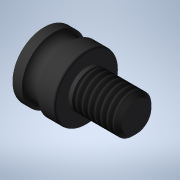
# Autodesk Inventor part: 101013DH-16-B1_ir
Saved by Autodesk Inventor 2021 (Build 250183000, 183)
## iProperties
Created: 2025-04-11
Part Number: 101013DH-16-B1_ir
Material: Generic
Catalog Web Link: www.cadenas.de
Description: DH-A,B,H ir-D-Series bearings
Vendor: TOKBEARING
Document SubType Name: Modeling
Designer: psAdmin
Manufacturer: TOKBEARING
Mass: 11800 g
Surface Area: 6.00448 cm^2
Volume: 0.745153 cm^3
Density: 1 g/cm^3
Appearance: PSOLRGB-175-175-175
Category: PARTsolutions
Company: TOKBEARING
Title: 101013DH-16-B1_ir
Author: Cadenas PARTsolutions
Comments: D-Series bearings
PSOL_IDENT_0: {$CADENAS_DATA/23d-libs/tok_bearing/d_series_bearings/dh_abh/dh_abh_ir.prj},181 {VTYP=3D},{NB=101013
PSOL_IDENT_1: DH-16-B1_ir},{LINA=101013DH-16-B1_ir},{NN=DH-A,B,H ir},{DATE=24.03.2025 06:05:05},{GEOMDATE=18.12.20
PSOL_IDENT_2: 12 09:46:00},{VERSION=},{LINEID=2630},{WBVAR=},{WBNUMERIC=}  {NB=101013DH-16-B1_ir},{LINA=101013DH-1
PSOL_IDENT_3: 6-B1_ir},{KT=DUMMY},{IDNR=},{CODE=101013},{PN=DH-16-B1},{D=19},{D1=16.0},{SD=-},{SDX=0.000},{SD1=-},
PSOL_IDENT_4: {SD1X=0.000},{W=6},{C=1},{CX=1.000},{L=8},{LX=8.000},{D2XT=-},{D2=0.000},{T=0.000},{G=2.1},{TYPE=2},
PSOL_IDENT_5: {QTY=2.000},{GW=11.8},{NDM=6.000},{BD=3},{OP=39.878},{N=6},{R=6.35},{GP=2.82}
NB: 101013DH-16-B1_ir
NN: DH-A,B,H ir
NT: D-Series bearings
NBSYN: $CODE.$PN._ir
LINA: 101013DH-16-B1_ir
CATALOG: TOK, Inc
CODE: 101013
PN: DH-16-B1
D: 19
D1: 16
SD: -
SD1: -
W: 6
C: 1
L: 8
D2XT: -
G: 2.1
TYPE: 2
QTY: 2.000
GW: 11.8
SUPPLIER: TOKBEARING
ARTICLENO: 101013DH-16-B1_ir
BOMINFO: 101013DH-16-B1_ir
CREATOR: CADENAS GmbH
Autodesk Inventor part; units mm, degrees
sketch "Sketch_2" plane through (0, 0, 0) normal (0, 0, 1) x (1, 0, 0)
  line L0 (15, 0) -> (0, 0)
  line L1 (0, 0) -> (0, 4.88)
  arc A0 (0.3, 5.18) -> (0, 4.88) centre (0.3, 4.88) ccw
  line L2 (0.3, 5.18) -> (1.701, 5.18)
  arc A1 (1.701, 5.18) -> (4.299, 5.18) centre (3, 5.93) ccw
  line L3 (4.299, 5.18) -> (6.7, 5.18)
  arc A2 (7, 4.88) -> (6.7, 5.18) centre (6.7, 4.88) ccw
  line L4 (7, 4.88) -> (7, 3)
  line L5 (7, 3) -> (14.3865, 3)
  line L6 (14.3865, 3) -> (15, 2.3865)
  line L7 (15, 2.3865) -> (15, 0)
  line L8 (15, 0) -> (0, 0)
  constraints: 18 end point, 6 point on circle, 3 centre point
revolve "Revolution1" add sketch "Sketch_2" angle 360 about axis through (15, 0, 0) along (1, 0, 0)
thread "Thread1" size "M6x1" class "6g" standard "ISO Metric profile" length 6.7865
sketch "Sketch_3" plane through (0, 0, 0) normal (0, 0, 1) x (1, 0, 0)
  line L0 (0, -3.5) -> (1.8209, -2.9084)
  line L1 (1.8209, -2.9084) -> (3.3, -0.3464)
  line L2 (3.3, -0.3464) -> (3.3, 0.3464)
  line L3 (3.3, 0.3464) -> (1.8209, 2.9084)
  line L4 (1.8209, 2.9084) -> (0, 3.5)
  line L5 (0, 3.5) -> (0, -3.5)
  constraints: 12 end point
extrude "Extrusion1" cut sketch "Sketch_3" along normal mid plane 0.8
sketch "Sketch_4" plane through (0, 0, 0) normal (0, 1, 0) x (-1, 0, 0)
  line L0 (0, 3.5) -> (-1.8209, 2.9084)
  line L1 (-1.8209, 2.9084) -> (-3.3, 0.3464)
  line L2 (-3.3, 0.3464) -> (-3.3, -0.3464)
  line L3 (-3.3, -0.3464) -> (-1.8209, -2.9084)
  line L4 (-1.8209, -2.9084) -> (0, -3.5)
  line L5 (0, -3.5) -> (0, 3.5)
  constraints: 12 end point
extrude "Extrusion2" cut sketch "Sketch_4" along normal mid plane 0.8
ref_plane "IR_Dummy_XY" through (0, 0, 0) normal (1, 0, 0) x (0, 0, -1)
ref_plane "IR_Dummy_YZ" through (0, 0, 0) normal (0, 0, -1) x (0, 1, 0)
ref_plane "IR_Dummy_ZX" through (0, 0, 0) normal (0, 1, 0) x (1, 0, 0)
ref_plane "IR_OR_XY" through (0, 0, 0) normal (1, 0, 0) x (0, 0, -1)
ref_plane "IR_OR_YZ" through (0, 0, 0) normal (0, 0, -1) x (0, 1, 0)
ref_plane "IR_OR_ZX" through (0, 0, 0) normal (0, 1, 0) x (1, 0, 0)
body "Solid1"
